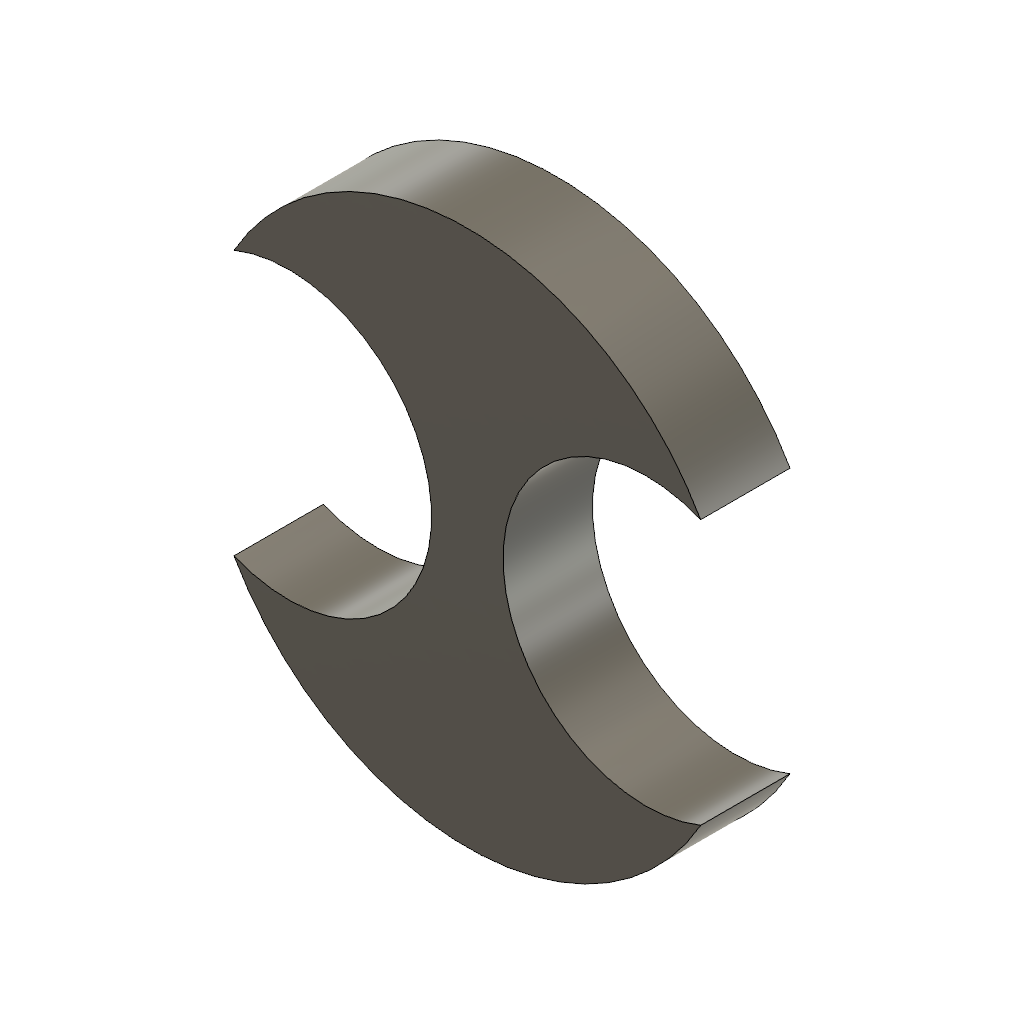
repeated_circle (Autodesk Fusion 360 design; units mm, degrees)
part number: 2026-10-21-11-33-16-306
Autodesk Fusion 360 part; units mm, degrees
sketch "TrimmedProfileSources" plane through (0, 0, 0) normal (0, 0, 1) x (1, 0, 0)
  circle A0 centre (0, 0) radius 30
  circle A1 centre (-20, 0) radius 16
  circle A2 centre (20, 0) radius 16
extrude "SelectedTrimmedProfile" add sketch "TrimmedProfileSources" along normal blind 10 contours A0 A1 A2
